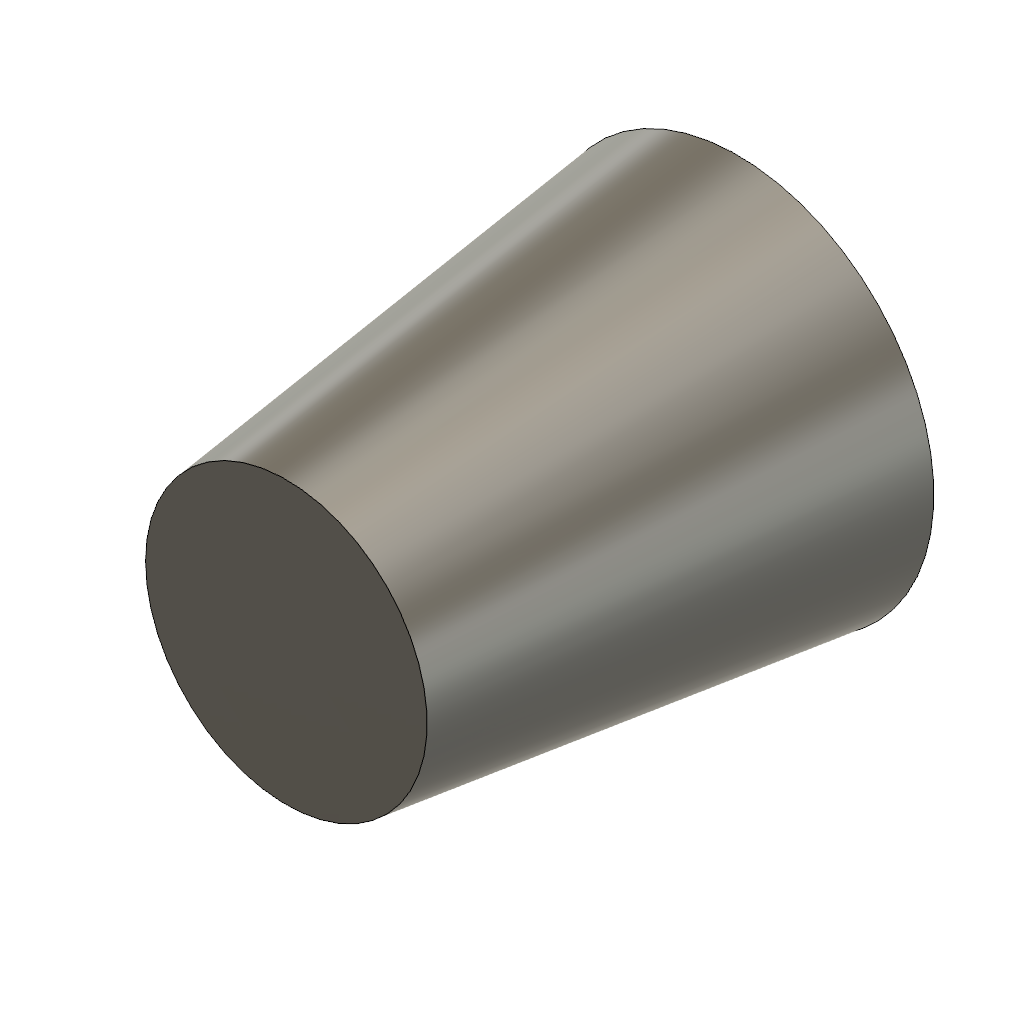
vendor_ProductionJournalDraftControlEdited (Autodesk Fusion 360 design; units mm, degrees)
part number: 2026-10-20-18-19-56-528
Autodesk Fusion 360 part; units mm, degrees
sketch "SeedProfile" plane through (0, 0, 0) normal (0, 0, 1) x (1, 0, 0)
  circle A0 centre (0, 0) radius 10
extrude "SeedExtrusion" add sketch "SeedProfile" along normal blind 23
draft "ProbeDraft" angle 7 neutral plane through (0, 0, 0) pull (0, 0, 1) 1 faces at (9.9876, -0.4985, 15.3333)
